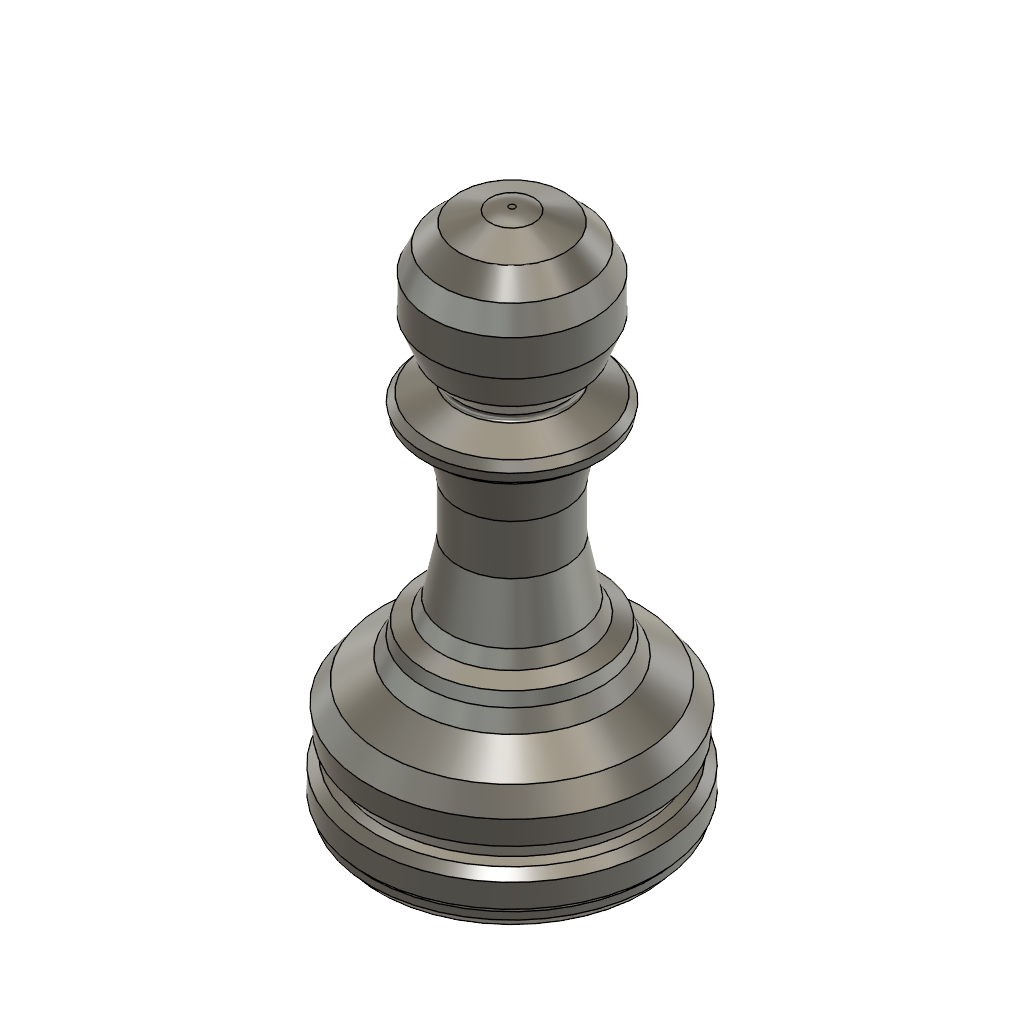
Simple Pawn (Autodesk Fusion 360 design; units mm, degrees)
part number: 2026-10-13-13-34-46-267
Autodesk Fusion 360 part; units mm, degrees
sketch "Sketch1" plane through (0, 0, 0) normal (1, 0, 0) x (0, 0, -1)
  line L0 (-0.0053, -17.729) -> (1.2282, -17.729)
  line L1 (1.2282, -17.729) -> (5, -17.5)
  line L2 (5, -17.5) -> (7.3961, -17.1698)
  line L3 (7.3961, -17.1698) -> (8.684, -16.9923)
  line L4 (8.684, -16.9923) -> (9.2382, -16.3474)
  line L5 (9.2382, -16.3474) -> (9.2382, -15.8704)
  line L6 (9.2382, -15.8704) -> (9.5278, -15.5336)
  line L7 (9.5278, -15.5336) -> (9.5278, -14)
  line L8 (9.5278, -14) -> (8.9611, -13.5131)
  line L9 (8.9611, -13.5131) -> (8.4323, -13.3046)
  line L10 (8.4323, -13.3046) -> (9.2444, -12.1533)
  line L11 (9.2444, -12.1533) -> (9.383, -10.525)
  line L12 (9.383, -10.525) -> (8.4323, -9.2091)
  line L13 (8.4323, -9.2091) -> (7.1598, -8.3116)
  line L14 (7.1598, -8.3116) -> (6.4164, -7.7872)
  line L15 (6.4164, -7.7872) -> (5.85, -6.6762)
  line L16 (5.85, -6.6762) -> (5.6527, -5.8538)
  line L17 (5.6527, -5.8538) -> (4.6658, -5.3933)
  line L18 (4.6658, -5.3933) -> (4.2015, -4.4825)
  line L19 (4.2015, -4.4825) -> (3.5, -1)
  line L20 (3.5, -1) -> (3.5, 2.2549)
  line L21 (3.5, 2.2549) -> (4.2015, 5.5608)
  line L22 (4.2015, 5.5608) -> (5.1592, 5.5608)
  line L23 (5.1592, 5.5608) -> (5.7184, 6.0378)
  line L24 (5.7184, 6.0378) -> (5.8486, 6.6512)
  line L25 (5.8486, 6.6512) -> (5.4388, 7.1316)
  line L26 (5.4388, 7.1316) -> (4.5, 7.5)
  line L27 (4.5, 7.5) -> (3.7306, 7.8019)
  line L28 (3.7306, 7.8019) -> (3.2099, 8.0063)
  line L29 (3.2099, 8.0063) -> (4.5, 9.5)
  line L30 (4.5, 9.5) -> (5.3466, 11.6575)
  line L31 (5.3466, 11.6575) -> (5.3466, 14)
  line L32 (5.3466, 14) -> (4.6822, 15.4952)
  line L33 (4.6822, 15.4952) -> (3.4487, 16.7781)
  line L34 (3.4487, 16.7781) -> (0.8335, 17.6828)
  line L35 (0.8335, 17.6828) -> (0, 17.6828)
  line L36 (-0.0053, -17.729) -> (0, 17.6828)
  constraint horizontal L0
  constraint parallel L2 L3
  constraint vertical L5
  constraint parallel L4 L6
  constraint parallel L5 L7
  constraint perpendicular L6 L8
  constraint perpendicular L10 L13
  constraint perpendicular L10 L14
  constraint parallel L15 L18
  constraint vertical L20
  constraint perpendicular L20 L22
  constraint parallel L21 L24
  constraint perpendicular L23 L25
  constraint parallel L26 L27
  constraint perpendicular L28 L30
  constraint vertical L31
  constraint horizontal L35
revolve "Revolve1" add sketch "Sketch1" angle 360 about axis through (0, -17.729, 0.0053) along (0, 1, -0.000151)
move_body "Move1" bodies 1 to x (1, 0, 0) y (0, 1, 0) z (0, 0, 1) at (0, 0, -28)
sketch "Sketch2" plane through (0, 0, 0) normal (0, 0, 1) x (1, 0, 0)
  line L0 (-8.7, -17) -> (8.5, -17)
  line L1 (8.5, -17) -> (8.5, -18)
  line L2 (8.5, -18) -> (-8.7, -18)
  line L3 (-8.7, -18) -> (-8.7, -17)
  constraint horizontal L0
  constraint vertical L1
  constraint horizontal L2
  constraint vertical L3
extrude "Extrude1" cut sketch "Sketch2" against normal blind 39
fillet "Fillet1" radius 0.25 1 edges at (-2.994, 8.0066, -29.1598)
fillet "Fillet2" radius 3.8 1 edges at (-0.7771, 17.6828, -28.3014)
sketch "Sketch3" plane through (0, -17, 0) normal (0, -1, 0) x (1, 0, 0)
  ellipse E0 centre (0, -28.0042) end of major axis (0, -36.6284) minor radius 8.6242 (8.5, -26.5458) -> (8.5, -29.4626) ccw
  line L0 (8.5, -29.4626) -> (8.5, -26.5458)
  circle A0 centre (0, -28.0042) radius 3.15
  dimension "d8" = 6.3
  constraint concentric E0 A0
  measures "d8" diameter of A0
extrude "Extrude2" cut sketch "Sketch3" against normal blind 2.2 contours A0
